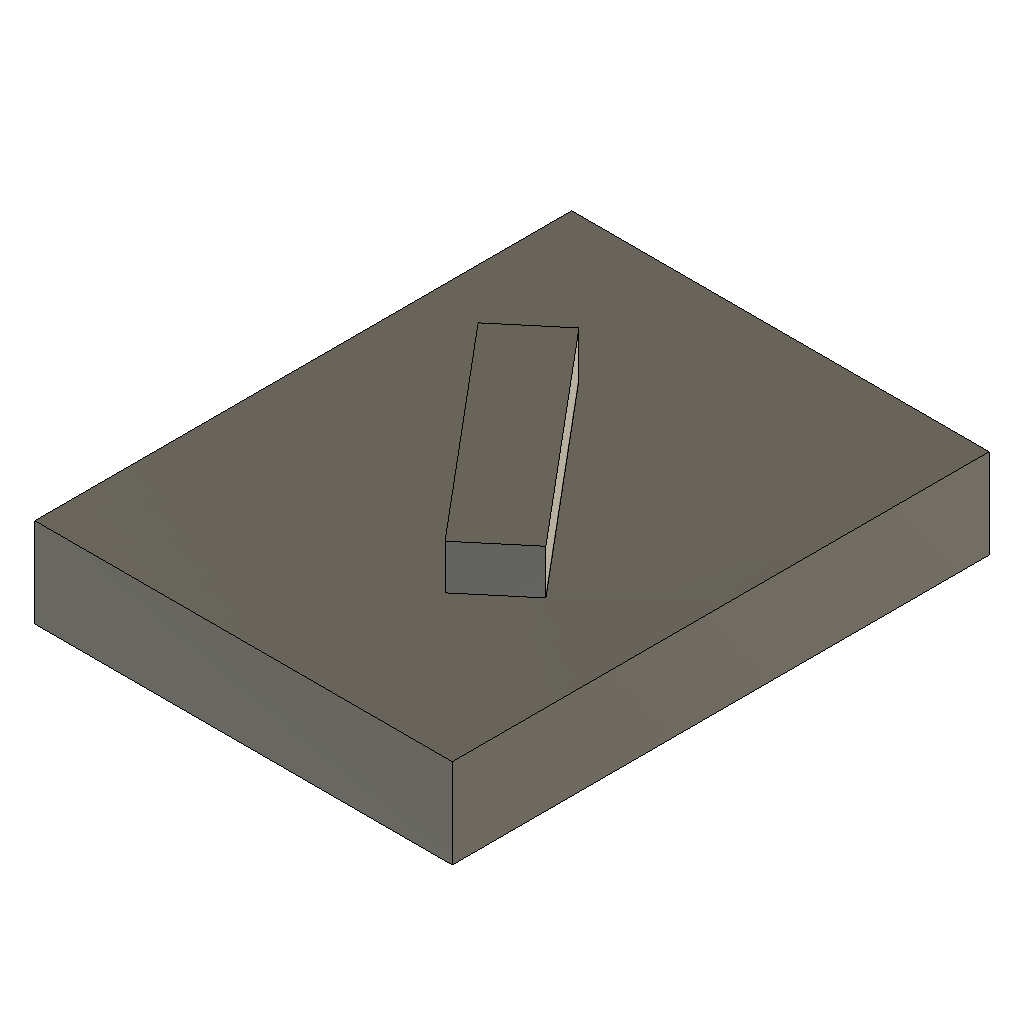
joint_revolute_limits (Autodesk Fusion 360 design; units mm, degrees)
part number: 2026-11-27-13-06-07-349
part number: 2026-11-27-13-09-57-152
Autodesk Fusion 360 part; units mm, degrees
sketch "Sketch1" plane through (0, 0, 0) normal (0, 0, 1) x (1, 0, 0)
  line L0 (0, 0) -> (46.6522, 0)
  line L1 (46.6522, 0) -> (46.6522, 60)
  line L2 (46.6522, 60) -> (0, 60)
  line L3 (0, 60) -> (0, 0)
  dimension "d1" = 60
  constraint horizontal L0
  constraint vertical L1
  constraint horizontal L2
  constraint vertical L3
  constraint coincident L0.start L3.end
  measures "d1" distance of L0.start L2.end
extrude "Extrude1" add sketch "Sketch1" along normal blind 10 makes body 1
sketch "Sketch2" plane through (0, 0, 10) normal (0, 0, 1) x (-1, 0, 0)
  line L0 (0, -60) -> (0, 0)
  line L1 (0, 0) -> (-46.6522, 0)
  line L2 (-46.6522, 0) -> (-46.6522, -60)
  line L3 (-46.6522, -60) -> (0, -60)
  line L4 (-6.3154, -11.3065) -> (-14.3154, -11.3065)
  line L5 (-14.3154, -11.3065) -> (-14.3154, -41.3065)
  line L6 (-14.3154, -41.3065) -> (-6.3154, -41.3065)
  line L7 (-6.3154, -41.3065) -> (-6.3154, -11.3065)
  dimension "d4" = 8
  dimension "d5" = 30
  constraint horizontal L4
  constraint vertical L5
  constraint horizontal L6
  constraint vertical L7
  measures "d4" distance of L4.start L4.end
  measures "d5" distance of L4.start L6.end
extrude "Extrude1'" add sketch "Sketch2" along normal blind 5 separate body contours L4 L5 L6 L7 makes body 2 in component "Component"
component "Component" placed x (1, 0, 0) y (0, -1, 0) z (0, 0, -1) at (13.0107, 56.3065, 25)
